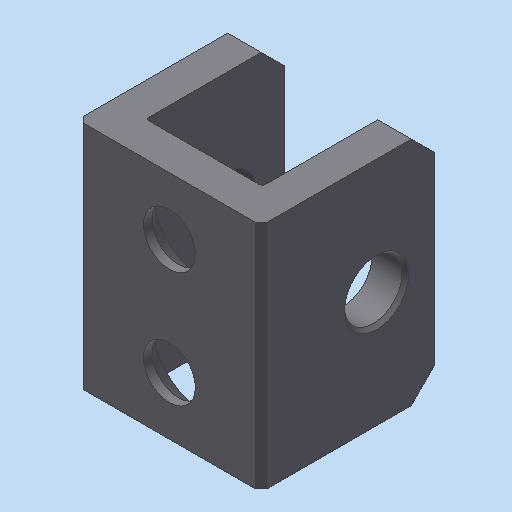
# Autodesk Inventor part: MM0861AN100_G01_115
Saved by Autodesk Inventor 2023.3 (Build 273359000, 359)
## iProperties
Created: 2018-10-29
Part Number: MM0861AN100_G01_115
Material: 1.2379 X155CrVMo 12-1
Document SubType Name: Modeling
Designer: Rose
Density: 7.85 g/cm^3
Appearance: Metall - Stahl
Description: =<RBPARTNOTITLE2>
Mass: 15.7971 g
Surface Area: 19.0812 cm^2
Volume: 2.01237 cm^3
RBMATERIAL: =<Material>
RBMATNO: =<Part Number>
RBPARTMADEOF: Präzi.Fl.20x15x19
RBPARTNOTITLE1: manufactured part
RBPARTNOTITLE2: Anfertigungsteil
MaxAbmaße: 0 x 0 x 0 (FM)
AnP_Material_aktuell: =<Material>
AnP_Kommentar_aktuell: =<Comments>
RBDRAWINGMISSINGSPEC: --
AnP_Kategorie: 1
AnP_Material: =<Material>
Author: Rose
Keywords: =<RBPARTMADEOF>
Comments: =<RBSURFACE2>
Revision Number: 01
Autodesk Inventor part; units mm, degrees
ref_plane "YZ Plane" through (0, 0, 0) normal (1, 0, 0) x (0, 1, 0)
ref_plane "XZ Plane" through (0, 0, 0) normal (0, 1, 0) x (-1, 0, 0)
ref_plane "XY Plane" through (0, 0, 0) normal (0, 0, 1) x (1, 0, 0)
sketch "Skizze1" plane through (0, 0, 0) normal (0, 0, 1) x (1, 0, 0)
  line L0 (0, 18) -> (0, -3) projected
  line L1 (-11.13, 0) -> (11.13, 0) projected
  line L2 (-7.95, 15) -> (-7.95, 0)
  line L3 (-7.95, 0) -> (7.95, 0)
  line L4 (7.95, 0) -> (7.95, 15)
  line L5 (7.95, 15) -> (5.05, 15)
  line L6 (5.05, 15) -> (5.05, 3)
  line L7 (5.05, 3) -> (-5.05, 3)
  line L8 (-5.05, 3) -> (-5.05, 15)
  line L9 (-5.05, 15) -> (-7.95, 15)
  dimension "d1" = 10.1
  dimension "d2" = 3
  dimension "d3" = 15
  dimension "d30" = 15.9
  constraints: 16 end point, 3 parallel, 3 perpendicular, 2 collinear, 2 point on line, 2 other
  measures "d1" distance between parallel lines of L6 L8
  measures "d2" distance between parallel lines of L1 L7
  measures "d3" distance between parallel lines of L1 L9
  measures "d30" distance between parallel lines of L4 L2
extrude "Extrusion1" add sketch "Skizze1" along normal mid plane 20
sketch "Skizze2" plane through (-5.05, 3, 10) normal (0, 1, 0) x (1, 0, 0)
  line L0 (5.05, 24) -> (5.05, -4) projected
  line L1 (16.18, 10) -> (-6.08, 10) projected
  point P0 (5.05, 15)
  point P1 (5.05, 5)
  dimension "d6" = 10
  constraints: 2 point on line, 1 symmetric about line
  measures "d6" distance of point (5.05, 5) point (5.05, 15)
hole "Bohrung1" at (0, 3, -5) at (0, 3, 5) direction (0, -1, 0) diameter 4.5 end through all countersink diameter 9 countersink angle 90
sketch "Skizze3" plane through (7.95, 0, 10) normal (1, 0, 0) x (0, 0, -1)
  line L0 (20, 15) -> (0, 15) projected
  line L1 (10, -3) -> (10, 18) projected
  point P0 (10, 10)
  dimension "d14" = 5
  dimension "d23" = 0
  measures "d14" distance from line of point (10, 10) L0
  measures "d23" horizontal distance of L1 point (10, 10)
hole "Bohrung2" at (7.95, 10, 0) direction (-1, 0, 0) diameter 5 end through all
chamfer "Fase1" distance 2 angle 45 4 edges at (-6.5, 15, 10) (6.5, 15, 10) (-6.5, 15, -10) (6.5, 15, -10)
chamfer "Fase2" distance 0.3 angle 45 2 edges at (7.95, 10, 2.5) (-7.95, 10, 2.5)
fillet "Rundung1" radius 0.3 2 edges at (-5.05, 3, 0) (5.05, 3, 0)
chamfer "Fase3" distance 0.5 angle 45 2 edges at (7.95, 0, 0) (-7.95, 0, 0)
